nrsk-left-case (Autodesk Fusion 360 design; units mm, degrees)
part number: 2026-11-08-22-34-04-126
part number: 2026-11-09-00-00-46-954
part number: 2026-11-09-00-00-51-869
part number: 2026-11-09-00-01-05-167
part number: 2026-11-09-00-01-07-833
part number: 2026-11-09-00-01-08-673
part number: 2026-11-09-00-01-09-551
part number: 2026-11-09-15-11-48-574
Autodesk Fusion 360 part; units mm, degrees
(part 1 of 3)
sketch "outline" plane through (0, 0, 0) normal (0, 0, 1) x (1, 0, 0) in component "tray"
  line L0 (1, -125.8) -> (154.125, -125.8)
  line L1 (166.625, -113.3) -> (166.625, 5)
  line L2 (154.125, 17.5) -> (1, 17.5)
  line L3 (-11.5, 5) -> (-11.5, -113.3)
  arc A0 (154.125, -125.8) -> (166.625, -113.3) centre (154.125, -113.3) ccw
  arc A1 (166.625, 5) -> (154.125, 17.5) centre (154.125, 5) ccw
  arc A2 (1, 17.5) -> (-11.5, 5) centre (1, 5) ccw
  arc A3 (-11.5, -113.3) -> (1, -125.8) centre (1, -113.3) ccw
extrude "Extrude1" add sketch "outline" along normal blind 14.1 makes body 1 in component "tray"
fillet "Fillet1" radius 2 64 edges at (-7.8388, -122.1388, 0) (77.5625, -125.8, 0) (162.9638, -122.1388, 0) (166.625, -54.15, 0) (162.9638, 13.8388, 0) (77.5625, 17.5, 0) (-7.8388, 13.8388, 0) (-11.5, -54.15, 0) (-11.5, -54.15, 0) (-7.8388, -122.1388, 0) (77.5625, -125.8, 0) (162.9638, -122.1388, 0) (166.625, -54.15, 0) (162.9638, 13.8388, 0) (77.5625, 17.5, 0) (-7.8388, 13.8388, 0) (-7.8388, 13.8388, 0) (-11.5, -54.15, 0) (-7.8388, -122.1388, 0) (77.5625, -125.8, 0) (162.9638, -122.1388, 0) (166.625, -54.15, 0) (162.9638, 13.8388, 0) (77.5625, 17.5, 0) (77.5625, 17.5, 0) (-7.8388, 13.8388, 0) (-11.5, -54.15, 0) (-7.8388, -122.1388, 0) (77.5625, -125.8, 0) (162.9638, -122.1388, 0) (166.625, -54.15, 0) (162.9638, 13.8388, 0) (162.9638, 13.8388, 0) (77.5625, 17.5, 0) (-7.8388, 13.8388, 0) (-11.5, -54.15, 0) (-7.8388, -122.1388, 0) (77.5625, -125.8, 0) (162.9638, -122.1388, 0) (166.625, -54.15, 0) (166.625, -54.15, 0) (162.9638, 13.8388, 0) (77.5625, 17.5, 0) (-7.8388, 13.8388, 0) (-11.5, -54.15, 0) (-7.8388, -122.1388, 0) (77.5625, -125.8, 0) (162.9638, -122.1388, 0) (162.9638, -122.1388, 0) (166.625, -54.15, 0) (162.9638, 13.8388, 0) (77.5625, 17.5, 0) (-7.8388, 13.8388, 0) (-11.5, -54.15, 0) (-7.8388, -122.1388, 0) (77.5625, -125.8, 0) (77.5625, -125.8, 0) (162.9638, -122.1388, 0) (166.625, -54.15, 0) (162.9638, 13.8388, 0) (77.5625, 17.5, 0) (-7.8388, 13.8388, 0) (-11.5, -54.15, 0) (-7.8388, -122.1388, 0) on bodies 1 in component "tray"
fillet "Fillet2" radius 0.6 64 edges at (-7.8388, -122.1388, 14.1) (77.5625, -125.8, 14.1) (162.9638, -122.1388, 14.1) (166.625, -54.15, 14.1) (162.9638, 13.8388, 14.1) (77.5625, 17.5, 14.1) (-7.8388, 13.8388, 14.1) (-11.5, -54.15, 14.1) (77.5625, -125.8, 14.1) (162.9638, -122.1388, 14.1) (166.625, -54.15, 14.1) (162.9638, 13.8388, 14.1) (77.5625, 17.5, 14.1) (-7.8388, 13.8388, 14.1) (-11.5, -54.15, 14.1) (-7.8388, -122.1388, 14.1) (162.9638, -122.1388, 14.1) (166.625, -54.15, 14.1) (162.9638, 13.8388, 14.1) (77.5625, 17.5, 14.1) (-7.8388, 13.8388, 14.1) (-11.5, -54.15, 14.1) (-7.8388, -122.1388, 14.1) (77.5625, -125.8, 14.1) (166.625, -54.15, 14.1) (162.9638, 13.8388, 14.1) (77.5625, 17.5, 14.1) (-7.8388, 13.8388, 14.1) (-11.5, -54.15, 14.1) (-7.8388, -122.1388, 14.1) (77.5625, -125.8, 14.1) (162.9638, -122.1388, 14.1) (162.9638, 13.8388, 14.1) (77.5625, 17.5, 14.1) (-7.8388, 13.8388, 14.1) (-11.5, -54.15, 14.1) (-7.8388, -122.1388, 14.1) (77.5625, -125.8, 14.1) (162.9638, -122.1388, 14.1) (166.625, -54.15, 14.1) (77.5625, 17.5, 14.1) (-7.8388, 13.8388, 14.1) (-11.5, -54.15, 14.1) (-7.8388, -122.1388, 14.1) (77.5625, -125.8, 14.1) (162.9638, -122.1388, 14.1) (166.625, -54.15, 14.1) (162.9638, 13.8388, 14.1) (-7.8388, 13.8388, 14.1) (-11.5, -54.15, 14.1) (-7.8388, -122.1388, 14.1) (77.5625, -125.8, 14.1) (162.9638, -122.1388, 14.1) (166.625, -54.15, 14.1) (162.9638, 13.8388, 14.1) (77.5625, 17.5, 14.1) (-11.5, -54.15, 14.1) (-7.8388, -122.1388, 14.1) (77.5625, -125.8, 14.1) (162.9638, -122.1388, 14.1) (166.625, -54.15, 14.1) (162.9638, 13.8388, 14.1) (77.5625, 17.5, 14.1) (-7.8388, 13.8388, 14.1) on bodies 1 in component "tray"
ref_plane "WorkPlane1" through (0, 0, 2) normal (0, 0, 1) x (1, 0, 0) in component "tray"
sketch "cavity" plane through (0, 0, 2) normal (0, 0, 1) x (1, 0, 0) in component "tray"
  line L0 (1, -117.8) -> (154.125, -117.8)
  line L1 (158.625, -113.3) -> (158.625, 5)
  line L2 (154.125, 9.5) -> (1, 9.5)
  line L3 (-3.5, 5) -> (-3.5, -113.3)
  arc A0 (154.125, -117.8) -> (158.625, -113.3) centre (154.125, -113.3) ccw
  arc A1 (158.625, 5) -> (154.125, 9.5) centre (154.125, 5) ccw
  arc A2 (1, 9.5) -> (-3.5, 5) centre (1, 5) ccw
  arc A3 (-3.5, -113.3) -> (1, -117.8) centre (1, -113.3) ccw
extrude "Extrude2" cut sketch "cavity" along normal blind 14.1 bodies 1 in component "tray"
sketch "bosses" plane through (0, 0, 2) normal (0, 0, 1) x (1, 0, 0) in component "tray"
  circle A0 centre (16, -19.05) radius 2.3
  circle A1 centre (56.5, -19.05) radius 2.3
  circle A2 centre (100.5, -19.05) radius 2.3
  circle A3 centre (132, -19.05) radius 2.3
  circle A4 centre (17, -95.25) radius 2.3
  circle A5 centre (58.5, -95.25) radius 2.3
  circle A6 centre (99.5, -95.25) radius 2.3
  circle A7 centre (142.5, -95.25) radius 2.3
  dimension "d2354" = 4.6
  dimension "d2355" = 4.6
  dimension "d2356" = 4.6
  dimension "d2357" = 4.6
  dimension "d2358" = 4.6
  dimension "d2359" = 4.6
  dimension "d2360" = 4.6
  dimension "d2361" = 4.6
  measures "d2354" diameter of A0
  measures "d2355" diameter of A1
  measures "d2356" diameter of A2
  measures "d2357" diameter of A3
  measures "d2358" diameter of A4
  measures "d2359" diameter of A5
  measures "d2360" diameter of A6
  measures "d2361" diameter of A7
extrude "Extrude3" add sketch "bosses" along normal blind 7 bodies 1 in component "tray"
ref_plane "WorkPlane2" through (0, 0, 0.6) normal (0, 0, 1) x (1, 0, 0) in component "tray"
sketch "pilot holes" plane through (0, 0, 0.6) normal (0, 0, 1) x (1, 0, 0) in component "tray"
  circle A0 centre (16, -19.05) radius 0.8
  circle A1 centre (56.5, -19.05) radius 0.8
  circle A2 centre (100.5, -19.05) radius 0.8
  circle A3 centre (132, -19.05) radius 0.8
  circle A4 centre (17, -95.25) radius 0.8
  circle A5 centre (58.5, -95.25) radius 0.8
  circle A6 centre (99.5, -95.25) radius 0.8
  circle A7 centre (142.5, -95.25) radius 0.8
  dimension "d2366" = 1.6
  dimension "d2367" = 1.6
  dimension "d2368" = 1.6
  dimension "d2369" = 1.6
  dimension "d2370" = 1.6
  dimension "d2371" = 1.6
  dimension "d2372" = 1.6
  dimension "d2373" = 1.6
  measures "d2366" diameter of A0
  measures "d2367" diameter of A1
  measures "d2368" diameter of A2
  measures "d2369" diameter of A3
  measures "d2370" diameter of A4
  measures "d2371" diameter of A5
  measures "d2372" diameter of A6
  measures "d2373" diameter of A7
extrude "Extrude4" cut sketch "pilot holes" along normal blind 8.4 bodies 1 in component "tray"
sketch "screw holes" plane through (0, 0, 0) normal (0, 0, 1) x (1, 0, 0) in component "tray"
  circle A0 centre (-5.0104, -119.3104) radius 1.1
  circle A1 centre (160.1354, -119.3104) radius 1.1
  circle A2 centre (49.2083, 13.5) radius 1.1
  circle A3 centre (49.2083, -121.8) radius 1.1
  circle A4 centre (105.9167, 13.5) radius 1.1
  circle A5 centre (105.9167, -121.8) radius 1.1
  circle A6 centre (-7.5, -54.15) radius 1.1
  circle A7 centre (162.625, -54.15) radius 1.1
  circle A8 centre (19.1438, 13.5) radius 1.1
  circle A9 centre (-7.5, -13.1438) radius 1.1
  dimension "d2376" = 2.2
  dimension "d2377" = 2.2
  dimension "d2378" = 2.2
  dimension "d2379" = 2.2
  dimension "d2380" = 2.2
  dimension "d2381" = 2.2
  dimension "d2382" = 2.2
  dimension "d2383" = 2.2
  dimension "d2384" = 2.2
  dimension "d2385" = 2.2
  measures "d2376" diameter of A0
  measures "d2377" diameter of A1
  measures "d2378" diameter of A2
  measures "d2379" diameter of A3
  measures "d2380" diameter of A4
  measures "d2381" diameter of A5
  measures "d2382" diameter of A6
  measures "d2383" diameter of A7
  measures "d2384" diameter of A8
  measures "d2385" diameter of A9
extrude "Extrude5" cut sketch "screw holes" along normal blind 14.12 bodies 1 in component "tray"
sketch "counterbores" plane through (0, 0, 0) normal (0, 0, 1) x (1, 0, 0) in component "tray"
  circle A0 centre (-5.0104, -119.3104) radius 2.3
  circle A1 centre (160.1354, -119.3104) radius 2.3
  circle A2 centre (49.2083, 13.5) radius 2.3
  circle A3 centre (49.2083, -121.8) radius 2.3
  circle A4 centre (105.9167, 13.5) radius 2.3
  circle A5 centre (105.9167, -121.8) radius 2.3
  circle A6 centre (-7.5, -54.15) radius 2.3
  circle A7 centre (162.625, -54.15) radius 2.3
  circle A8 centre (19.1438, 13.5) radius 2.3
  circle A9 centre (-7.5, -13.1438) radius 2.3
  dimension "d2388" = 4.6
  dimension "d2389" = 4.6
  dimension "d2390" = 4.6
  dimension "d2391" = 4.6
  dimension "d2392" = 4.6
  dimension "d2393" = 4.6
  dimension "d2394" = 4.6
  dimension "d2395" = 4.6
  dimension "d2396" = 4.6
  dimension "d2397" = 4.6
  measures "d2388" diameter of A0
  measures "d2389" diameter of A1
  measures "d2390" diameter of A2
  measures "d2391" diameter of A3
  measures "d2392" diameter of A4
  measures "d2393" diameter of A5
  measures "d2394" diameter of A6
  measures "d2395" diameter of A7
  measures "d2396" diameter of A8
  measures "d2397" diameter of A9
extrude "Extrude6" cut sketch "counterbores" along normal blind 1.6 bodies 1 in component "tray"
ref_plane "WorkPlane3" through (0, 0, 10.9) normal (0, 0, 1) x (1, 0, 0) in component "tray"
sketch "boss pockets" plane through (0, 0, 10.9) normal (0, 0, 1) x (1, 0, 0) in component "tray"
  circle A0 centre (-5.0104, -119.3104) radius 3
  circle A1 centre (160.1354, -119.3104) radius 3
  circle A2 centre (49.2083, 13.5) radius 3
  circle A3 centre (49.2083, -121.8) radius 3
  circle A4 centre (105.9167, 13.5) radius 3
  circle A5 centre (105.9167, -121.8) radius 3
  circle A6 centre (-7.5, -54.15) radius 3
  circle A7 centre (162.625, -54.15) radius 3
  circle A8 centre (19.1438, 13.5) radius 3
  circle A9 centre (-7.5, -13.1438) radius 3
  dimension "d2402" = 6
  dimension "d2403" = 6
  dimension "d2404" = 6
  dimension "d2405" = 6
  dimension "d2406" = 6
  dimension "d2407" = 6
  dimension "d2408" = 6
  dimension "d2409" = 6
  dimension "d2410" = 6
  dimension "d2411" = 6
  measures "d2402" diameter of A0
  measures "d2403" diameter of A1
  measures "d2404" diameter of A2
  measures "d2405" diameter of A3
  measures "d2406" diameter of A4
  measures "d2407" diameter of A5
  measures "d2408" diameter of A6
  measures "d2409" diameter of A7
  measures "d2410" diameter of A8
  measures "d2411" diameter of A9
extrude "Extrude7" cut sketch "boss pockets" along normal blind 3.21 bodies 1 in component "tray"
ref_plane "WorkPlane4" through (0, 0, 9.1) normal (0, 0, 1) x (1, 0, 0) in component "tray"
sketch "nut traps" plane through (0, 0, 9.1) normal (0, 0, 1) x (1, 0, 0) in component "tray"
  line L0 (-2.6144, -119.3104) -> (-3.8124, -117.2354)
  line L1 (-3.8124, -117.2354) -> (-6.2084, -117.2354)
  line L2 (-6.2084, -117.2354) -> (-7.4064, -119.3104)
  line L3 (-7.4064, -119.3104) -> (-6.2084, -121.3854)
  line L4 (-6.2084, -121.3854) -> (-3.8124, -121.3854)
  line L5 (-3.8124, -121.3854) -> (-2.6144, -119.3104)
  line L6 (162.5314, -119.3104) -> (161.3334, -117.2354)
  line L7 (161.3334, -117.2354) -> (158.9374, -117.2354)
  line L8 (158.9374, -117.2354) -> (157.7394, -119.3104)
  line L9 (157.7394, -119.3104) -> (158.9374, -121.3854)
  line L10 (158.9374, -121.3854) -> (161.3334, -121.3854)
  line L11 (161.3334, -121.3854) -> (162.5314, -119.3104)
  line L12 (51.6043, 13.5) -> (50.4063, 15.575)
  line L13 (50.4063, 15.575) -> (48.0103, 15.575)
  line L14 (48.0103, 15.575) -> (46.8123, 13.5)
  line L15 (46.8123, 13.5) -> (48.0103, 11.425)
  line L16 (48.0103, 11.425) -> (50.4063, 11.425)
  line L17 (50.4063, 11.425) -> (51.6043, 13.5)
  line L18 (51.6043, -121.8) -> (50.4063, -119.725)
  line L19 (50.4063, -119.725) -> (48.0103, -119.725)
  line L20 (48.0103, -119.725) -> (46.8123, -121.8)
  line L21 (46.8123, -121.8) -> (48.0103, -123.875)
  line L22 (48.0103, -123.875) -> (50.4063, -123.875)
  line L23 (50.4063, -123.875) -> (51.6043, -121.8)
  line L24 (108.3127, 13.5) -> (107.1147, 15.575)
  line L25 (107.1147, 15.575) -> (104.7187, 15.575)
  line L26 (104.7187, 15.575) -> (103.5207, 13.5)
  line L27 (103.5207, 13.5) -> (104.7187, 11.425)
  line L28 (104.7187, 11.425) -> (107.1147, 11.425)
  line L29 (107.1147, 11.425) -> (108.3127, 13.5)
  line L30 (108.3127, -121.8) -> (107.1147, -119.725)
  line L31 (107.1147, -119.725) -> (104.7187, -119.725)
  line L32 (104.7187, -119.725) -> (103.5207, -121.8)
  line L33 (103.5207, -121.8) -> (104.7187, -123.875)
  line L34 (104.7187, -123.875) -> (107.1147, -123.875)
  line L35 (107.1147, -123.875) -> (108.3127, -121.8)
  line L36 (-5.104, -54.15) -> (-6.302, -52.075)
  line L37 (-6.302, -52.075) -> (-8.698, -52.075)
  line L38 (-8.698, -52.075) -> (-9.896, -54.15)
  line L39 (-9.896, -54.15) -> (-8.698, -56.225)
  line L40 (-8.698, -56.225) -> (-6.302, -56.225)
  line L41 (-6.302, -56.225) -> (-5.104, -54.15)
  line L42 (165.021, -54.15) -> (163.823, -52.075)
  line L43 (163.823, -52.075) -> (161.427, -52.075)
  line L44 (161.427, -52.075) -> (160.229, -54.15)
  line L45 (160.229, -54.15) -> (161.427, -56.225)
  line L46 (161.427, -56.225) -> (163.823, -56.225)
  line L47 (163.823, -56.225) -> (165.021, -54.15)
  line L48 (21.5398, 13.5) -> (20.3418, 15.575)
  line L49 (20.3418, 15.575) -> (17.9458, 15.575)
  line L50 (17.9458, 15.575) -> (16.7478, 13.5)
  line L51 (16.7478, 13.5) -> (17.9458, 11.425)
  line L52 (17.9458, 11.425) -> (20.3418, 11.425)
  line L53 (20.3418, 11.425) -> (21.5398, 13.5)
  line L54 (-5.104, -13.1438) -> (-6.302, -11.0688)
  line L55 (-6.302, -11.0688) -> (-8.698, -11.0688)
  line L56 (-8.698, -11.0688) -> (-9.896, -13.1438)
  line L57 (-9.896, -13.1438) -> (-8.698, -15.2188)
  line L58 (-8.698, -15.2188) -> (-6.302, -15.2188)
  line L59 (-6.302, -15.2188) -> (-5.104, -13.1438)
  constraint coincident L0.end L1.start
  constraint coincident L1.end L2.start
  constraint coincident L2.end L3.start
  constraint coincident L3.end L4.start
  constraint coincident L4.end L5.start
  constraint coincident L0.start L5.end
  constraint coincident L6.end L7.start
  constraint coincident L7.end L8.start
  constraint coincident L8.end L9.start
  constraint coincident L9.end L10.start
  constraint coincident L10.end L11.start
  constraint coincident L6.start L11.end
  constraint coincident L12.end L13.start
  constraint coincident L13.end L14.start
  constraint coincident L14.end L15.start
  constraint coincident L15.end L16.start
  constraint coincident L16.end L17.start
  constraint coincident L12.start L17.end
  constraint coincident L18.end L19.start
  constraint coincident L19.end L20.start
  constraint coincident L20.end L21.start
  constraint coincident L21.end L22.start
  constraint coincident L22.end L23.start
  constraint coincident L18.start L23.end
  constraint coincident L24.end L25.start
  constraint coincident L25.end L26.start
  constraint coincident L26.end L27.start
  constraint coincident L27.end L28.start
  constraint coincident L28.end L29.start
  constraint coincident L24.start L29.end
  constraint coincident L30.end L31.start
  constraint coincident L31.end L32.start
  constraint coincident L32.end L33.start
  constraint coincident L33.end L34.start
  constraint coincident L34.end L35.start
  constraint coincident L30.start L35.end
  constraint coincident L36.end L37.start
  constraint coincident L37.end L38.start
  constraint coincident L38.end L39.start
  constraint coincident L39.end L40.start
  constraint coincident L40.end L41.start
  constraint coincident L36.start L41.end
  constraint coincident L42.end L43.start
  constraint coincident L43.end L44.start
  constraint coincident L44.end L45.start
  constraint coincident L45.end L46.start
  constraint coincident L46.end L47.start
  constraint coincident L42.start L47.end
  constraint coincident L48.end L49.start
  constraint coincident L49.end L50.start
  constraint coincident L50.end L51.start
  constraint coincident L51.end L52.start
  constraint coincident L52.end L53.start
  constraint coincident L48.start L53.end
  constraint coincident L54.end L55.start
  constraint coincident L55.end L56.start
  constraint coincident L56.end L57.start
  constraint coincident L57.end L58.start
  constraint coincident L58.end L59.start
  constraint coincident L54.start L59.end
extrude "Extrude8" cut sketch "nut traps" along normal blind 1.81 bodies 1 in component "tray"
ref_plane "WorkPlane5" through (0, 0, 2) normal (0, 0, 1) x (1, 0, 0) in component "tray"
sketch "wheel opening" plane through (0, 0, 2) normal (0, 0, 1) x (1, 0, 0) in component "tray"
  circle A0 centre (2, 4) radius 15.2
extrude "Extrude9" cut sketch "wheel opening" along normal blind 4.8 bodies 1 in component "tray"
ref_plane "WorkPlane6" through (0, 0, 6.8) normal (0, 0, 1) x (1, 0, 0) in component "tray"
sketch "cap lower tier" plane through (0, 0, 6.8) normal (0, 0, 1) x (1, 0, 0) in component "tray"
  circle A0 centre (2, 4) radius 15.2
extrude "Extrude10" cut sketch "cap lower tier" along normal blind 4.3 bodies 1 in component "tray"
ref_plane "WorkPlane7" through (0, 0, 11.1) normal (0, 0, 1) x (1, 0, 0) in component "tray"
sketch "cap shoulder" plane through (0, 0, 11.1) normal (0, 0, 1) x (1, 0, 0) in component "tray"
  circle A0 centre (2, 4) radius 17.2
extrude "Extrude11" cut sketch "cap shoulder" along normal blind 3.1 bodies 1 in component "tray"
ref_plane "WorkPlane8" through (0, 0, 13.6) normal (0, 0, 1) x (1, 0, 0) in component "tray"
sketch "cover step" plane through (0, 0, 13.6) normal (0, 0, 1) x (1, 0, 0) in component "tray"
  line L0 (145.325, -35.995) -> (154.125, -35.995)
  line L1 (161.225, -28.895) -> (161.225, 5)
  line L2 (154.125, 12.1) -> (145.325, 12.1)
  line L3 (138.225, 5) -> (138.225, -28.895)
  arc A0 (154.125, -35.995) -> (161.225, -28.895) centre (154.125, -28.895) ccw
  arc A1 (161.225, 5) -> (154.125, 12.1) centre (154.125, 5) ccw
  arc A2 (145.325, 12.1) -> (138.225, 5) centre (145.325, 5) ccw
  arc A3 (138.225, -28.895) -> (145.325, -35.995) centre (145.325, -28.895) ccw
extrude "Extrude12" cut sketch "cover step" along normal blind 0.51 bodies 1 in component "tray"
ref_plane "WorkPlane9" through (0, 0, 5.54) normal (0, 0, 1) x (1, 0, 0) in component "tray"
sketch "usb tunnel" plane through (0, 0, 5.54) normal (0, 0, 1) x (1, 0, 0) in component "tray"
  line L0 (128.79, 8.7) -> (129.425, 8.7)
  line L1 (129.425, 8.7) -> (129.425, 16.5)
  line L2 (129.425, 16.5) -> (128.79, 16.5)
  line L3 (128.79, 16.5) -> (128.79, 16.7)
  line L4 (128.79, 16.7) -> (117.46, 16.7)
  line L5 (117.46, 16.7) -> (117.46, 16.5)
  line L6 (117.46, 16.5) -> (116.825, 16.5)
  line L7 (116.825, 16.5) -> (116.825, 8.7)
  line L8 (116.825, 8.7) -> (117.46, 8.7)
  line L9 (117.46, 8.7) -> (117.46, 6.89)
  line L10 (117.46, 6.89) -> (128.79, 6.89)
  line L11 (128.79, 6.89) -> (128.79, 8.7)
  constraint coincident L0.end L1.start
  constraint coincident L1.end L2.start
  constraint coincident L2.end L3.start
  constraint coincident L3.end L4.start
  constraint coincident L4.end L5.start
  constraint coincident L5.end L6.start
  constraint coincident L6.end L7.start
  constraint coincident L7.end L8.start
  constraint coincident L8.end L9.start
  constraint coincident L9.end L10.start
  constraint coincident L10.end L11.start
  constraint coincident L0.start L11.end
extrude "Extrude13" cut sketch "usb tunnel" along normal blind 7.36 bodies 1 in component "tray"
ref_plane "WorkPlane10" through (0, 15.7, 0) normal (0, 1, 0) x (0, 0, 1) in component "tray"
sketch "usb opening" plane through (0, 15.7, 0) normal (0, 1, 0) x (1, 0, 0) in component "tray"
  line L0 (120.285, -5.54) -> (125.965, -5.54)
  line L1 (125.965, -9.2) -> (120.285, -9.2)
  arc A0 (125.965, -9.2) -> (125.965, -5.54) centre (125.965, -7.37) ccw
  arc A1 (120.285, -5.54) -> (120.285, -9.2) centre (120.285, -7.37) ccw
extrude "Extrude14" cut sketch "usb opening" along normal blind 2.8 bodies 1 in component "tray"
ref_plane "WorkPlane11" through (0, 0, 5.54) normal (0, 0, 1) x (1, 0, 0) in component "tray"
sketch "link tunnel" plane through (0, 0, 5.54) normal (0, 0, 1) x (1, 0, 0) in component "tray"
  line L0 (146.79, 8.7) -> (147.425, 8.7)
  line L1 (147.425, 8.7) -> (147.425, 16.5)
  line L2 (147.425, 16.5) -> (146.79, 16.5)
  line L3 (146.79, 16.5) -> (146.79, 16.7)
  line L4 (146.79, 16.7) -> (135.46, 16.7)
  line L5 (135.46, 16.7) -> (135.46, 16.5)
  line L6 (135.46, 16.5) -> (134.825, 16.5)
  line L7 (134.825, 16.5) -> (134.825, 8.7)
  line L8 (134.825, 8.7) -> (135.46, 8.7)
  line L9 (135.46, 8.7) -> (135.46, 6.89)
  line L10 (135.46, 6.89) -> (146.79, 6.89)
  line L11 (146.79, 6.89) -> (146.79, 8.7)
  constraint coincident L0.end L1.start
  constraint coincident L1.end L2.start
  constraint coincident L2.end L3.start
  constraint coincident L3.end L4.start
  constraint coincident L4.end L5.start
  constraint coincident L5.end L6.start
  constraint coincident L6.end L7.start
  constraint coincident L7.end L8.start
  constraint coincident L8.end L9.start
  constraint coincident L9.end L10.start
  constraint coincident L10.end L11.start
  constraint coincident L0.start L11.end
extrude "Extrude15" cut sketch "link tunnel" along normal blind 7.36 bodies 1 in component "tray"
ref_plane "WorkPlane12" through (0, 15.7, 0) normal (0, 1, 0) x (0, 0, 1) in component "tray"
sketch "link opening" plane through (0, 15.7, 0) normal (0, 1, 0) x (1, 0, 0) in component "tray"
  line L0 (138.285, -5.54) -> (143.965, -5.54)
  line L1 (143.965, -9.2) -> (138.285, -9.2)
  arc A0 (143.965, -9.2) -> (143.965, -5.54) centre (143.965, -7.37) ccw
  arc A1 (138.285, -5.54) -> (138.285, -9.2) centre (138.285, -7.37) ccw
extrude "Extrude16" cut sketch "link opening" along normal blind 2.8 bodies 1 in component "tray"
sketch "wheel post" plane through (0, 0, 2) normal (0, 0, 1) x (1, 0, 0) in component "tray"
  circle A0 centre (2, 4) radius 1.8
  dimension "d2450" = 3.6
  measures "d2450" diameter of A0
extrude "Extrude17" add sketch "wheel post" along normal blind 2 bodies 1 in component "tray"
sketch "reset" plane through (0, 0, 0) normal (0, 0, 1) x (1, 0, 0) in component "tray"
  circle A0 centre (136.125, -35.95) radius 1.5
  dimension "d2453" = 3
  measures "d2453" diameter of A0
extrude "Extrude18" cut sketch "reset" along normal blind 2.02 bodies 1 in component "tray"
sketch "foot recesses" plane through (0, 0, 0) normal (0, 0, 1) x (1, 0, 0) in component "tray"
  circle A0 centre (26.5, 9.5) radius 5
  circle A1 centre (156.125, 9.5) radius 5
  circle A2 centre (3.5, -117.8) radius 5
  circle A3 centre (151.625, -117.8) radius 5
  circle A4 centre (-3.5, -20.5) radius 5
  dimension "d2456" = 10
  dimension "d2457" = 10
  dimension "d2458" = 10
  dimension "d2459" = 10
  dimension "d2460" = 10
  measures "d2456" diameter of A0
  measures "d2457" diameter of A1
  measures "d2458" diameter of A2
  measures "d2459" diameter of A3
  measures "d2460" diameter of A4
extrude "Extrude19" cut sketch "foot recesses" along normal blind 1 bodies 1 in component "tray"
sketch "outline (2)" plane through (0, 0, 0) normal (0, 0, 1) x (1, 0, 0) in component "plate"
  line L0 (1, -125.8) -> (154.125, -125.8)
  line L1 (166.625, -113.3) -> (166.625, 5)
  line L2 (154.125, 17.5) -> (1, 17.5)
  line L3 (-11.5, 5) -> (-11.5, -113.3)
  arc A0 (154.125, -125.8) -> (166.625, -113.3) centre (154.125, -113.3) ccw
  arc A1 (166.625, 5) -> (154.125, 17.5) centre (154.125, 5) ccw
  arc A2 (1, 17.5) -> (-11.5, 5) centre (1, 5) ccw
  arc A3 (-11.5, -113.3) -> (1, -125.8) centre (1, -113.3) ccw
extrude "Extrude1'" add sketch "outline (2)" along normal blind 1.5 separate body makes body 2 in component "plate"
fillet "Fillet1'" radius 1 64 edges at (-7.8388, -122.1388, 1.5) (77.5625, -125.8, 1.5) (162.9638, -122.1388, 1.5) (166.625, -54.15, 1.5) (162.9638, 13.8388, 1.5) (77.5625, 17.5, 1.5) (-7.8388, 13.8388, 1.5) (-11.5, -54.15, 1.5) (77.5625, -125.8, 1.5) (162.9638, -122.1388, 1.5) (166.625, -54.15, 1.5) (162.9638, 13.8388, 1.5) (77.5625, 17.5, 1.5) (-7.8388, 13.8388, 1.5) (-11.5, -54.15, 1.5) (-7.8388, -122.1388, 1.5) (162.9638, -122.1388, 1.5) (166.625, -54.15, 1.5) (162.9638, 13.8388, 1.5) (77.5625, 17.5, 1.5) (-7.8388, 13.8388, 1.5) (-11.5, -54.15, 1.5) (-7.8388, -122.1388, 1.5) (77.5625, -125.8, 1.5) (166.625, -54.15, 1.5) (162.9638, 13.8388, 1.5) (77.5625, 17.5, 1.5) (-7.8388, 13.8388, 1.5) (-11.5, -54.15, 1.5) (-7.8388, -122.1388, 1.5) (77.5625, -125.8, 1.5) (162.9638, -122.1388, 1.5) (162.9638, 13.8388, 1.5) (77.5625, 17.5, 1.5) (-7.8388, 13.8388, 1.5) (-11.5, -54.15, 1.5) (-7.8388, -122.1388, 1.5) (77.5625, -125.8, 1.5) (162.9638, -122.1388, 1.5) (166.625, -54.15, 1.5) (77.5625, 17.5, 1.5) (-7.8388, 13.8388, 1.5) (-11.5, -54.15, 1.5) (-7.8388, -122.1388, 1.5) (77.5625, -125.8, 1.5) (162.9638, -122.1388, 1.5) (166.625, -54.15, 1.5) (162.9638, 13.8388, 1.5) (-7.8388, 13.8388, 1.5) (-11.5, -54.15, 1.5) (-7.8388, -122.1388, 1.5) (77.5625, -125.8, 1.5) (162.9638, -122.1388, 1.5) (166.625, -54.15, 1.5) (162.9638, 13.8388, 1.5) (77.5625, 17.5, 1.5) (-11.5, -54.15, 1.5) (-7.8388, -122.1388, 1.5) (77.5625, -125.8, 1.5) (162.9638, -122.1388, 1.5) (166.625, -54.15, 1.5) (162.9638, 13.8388, 1.5) (77.5625, 17.5, 1.5) (-7.8388, 13.8388, 1.5) on bodies 2 in component "plate"
sketch "switch cut-outs" plane through (0, 0, 0) normal (0, 0, 1) x (1, 0, 0) in component "plate"
  line L0 (2.525, -16.525) -> (16.525, -16.525)
  line L1 (16.525, -16.525) -> (16.525, -2.525)
  line L2 (16.525, -2.525) -> (2.525, -2.525)
  line L3 (2.525, -2.525) -> (2.525, -16.525)
  line L4 (21.575, -16.525) -> (35.575, -16.525)
  line L5 (35.575, -16.525) -> (35.575, -2.525)
  line L6 (35.575, -2.525) -> (21.575, -2.525)
  line L7 (21.575, -2.525) -> (21.575, -16.525)
  line L8 (40.625, -16.525) -> (54.625, -16.525)
  line L9 (54.625, -16.525) -> (54.625, -2.525)
  line L10 (54.625, -2.525) -> (40.625, -2.525)
  line L11 (40.625, -2.525) -> (40.625, -16.525)
  line L12 (59.675, -16.525) -> (73.675, -16.525)
  line L13 (73.675, -16.525) -> (73.675, -2.525)
  line L14 (73.675, -2.525) -> (59.675, -2.525)
  line L15 (59.675, -2.525) -> (59.675, -16.525)
  line L16 (78.725, -16.525) -> (92.725, -16.525)
  line L17 (92.725, -16.525) -> (92.725, -2.525)
  line L18 (92.725, -2.525) -> (78.725, -2.525)
  line L19 (78.725, -2.525) -> (78.725, -16.525)
  line L20 (97.775, -16.525) -> (111.775, -16.525)
  line L21 (111.775, -16.525) -> (111.775, -2.525)
  line L22 (111.775, -2.525) -> (97.775, -2.525)
  line L23 (97.775, -2.525) -> (97.775, -16.525)
  line L24 (116.825, -16.525) -> (130.825, -16.525)
  line L25 (130.825, -16.525) -> (130.825, -2.525)
  line L26 (130.825, -2.525) -> (116.825, -2.525)
  line L27 (116.825, -2.525) -> (116.825, -16.525)
  line L28 (2.525, -35.575) -> (16.525, -35.575)
  line L29 (16.525, -35.575) -> (16.525, -21.575)
  line L30 (16.525, -21.575) -> (2.525, -21.575)
  line L31 (2.525, -21.575) -> (2.525, -35.575)
  line L32 (21.575, -35.575) -> (35.575, -35.575)
  line L33 (35.575, -35.575) -> (35.575, -21.575)
  line L34 (35.575, -21.575) -> (21.575, -21.575)
  line L35 (21.575, -21.575) -> (21.575, -35.575)
  line L36 (40.625, -35.575) -> (54.625, -35.575)
  line L37 (54.625, -35.575) -> (54.625, -21.575)
  line L38 (54.625, -21.575) -> (40.625, -21.575)
  line L39 (40.625, -21.575) -> (40.625, -35.575)
  line L40 (59.675, -35.575) -> (73.675, -35.575)
  line L41 (73.675, -35.575) -> (73.675, -21.575)
  line L42 (73.675, -21.575) -> (59.675, -21.575)
  line L43 (59.675, -21.575) -> (59.675, -35.575)
  line L44 (78.725, -35.575) -> (92.725, -35.575)
  line L45 (92.725, -35.575) -> (92.725, -21.575)
  line L46 (92.725, -21.575) -> (78.725, -21.575)
  line L47 (78.725, -21.575) -> (78.725, -35.575)
  line L48 (97.775, -35.575) -> (111.775, -35.575)
  line L49 (111.775, -35.575) -> (111.775, -21.575)
  line L50 (111.775, -21.575) -> (97.775, -21.575)
  line L51 (97.775, -21.575) -> (97.775, -35.575)
  line L52 (116.825, -35.575) -> (130.825, -35.575)
  line L53 (130.825, -35.575) -> (130.825, -21.575)
  line L54 (130.825, -21.575) -> (116.825, -21.575)
  line L55 (116.825, -21.575) -> (116.825, -35.575)
  line L56 (7.288, -54.625) -> (21.288, -54.625)
  line L57 (21.288, -54.625) -> (21.288, -40.625)
  line L58 (21.288, -40.625) -> (7.288, -40.625)
  line L59 (7.288, -40.625) -> (7.288, -54.625)
  line L60 (31.1, -54.625) -> (45.1, -54.625)
  line L61 (45.1, -54.625) -> (45.1, -40.625)
  line L62 (45.1, -40.625) -> (31.1, -40.625)
  line L63 (31.1, -40.625) -> (31.1, -54.625)
  line L64 (50.15, -54.625) -> (64.15, -54.625)
  line L65 (64.15, -54.625) -> (64.15, -40.625)
  line L66 (64.15, -40.625) -> (50.15, -40.625)
  line L67 (50.15, -40.625) -> (50.15, -54.625)
  line L68 (69.2, -54.625) -> (83.2, -54.625)
  line L69 (83.2, -54.625) -> (83.2, -40.625)
  line L70 (83.2, -40.625) -> (69.2, -40.625)
  line L71 (69.2, -40.625) -> (69.2, -54.625)
  line L72 (88.25, -54.625) -> (102.25, -54.625)
  line L73 (102.25, -54.625) -> (102.25, -40.625)
  line L74 (102.25, -40.625) -> (88.25, -40.625)
  line L75 (88.25, -40.625) -> (88.25, -54.625)
  line L76 (107.3, -54.625) -> (121.3, -54.625)
  line L77 (121.3, -54.625) -> (121.3, -40.625)
  line L78 (121.3, -40.625) -> (107.3, -40.625)
  line L79 (107.3, -40.625) -> (107.3, -54.625)
  line L80 (9.669, -73.675) -> (23.669, -73.675)
  line L81 (23.669, -73.675) -> (23.669, -59.675)
  line L82 (23.669, -59.675) -> (9.669, -59.675)
  line L83 (9.669, -59.675) -> (9.669, -73.675)
  line L84 (35.863, -73.675) -> (49.863, -73.675)
  line L85 (49.863, -73.675) -> (49.863, -59.675)
  line L86 (49.863, -59.675) -> (35.863, -59.675)
  line L87 (35.863, -59.675) -> (35.863, -73.675)
  line L88 (54.913, -73.675) -> (68.913, -73.675)
  line L89 (68.913, -73.675) -> (68.913, -59.675)
  line L90 (68.913, -59.675) -> (54.913, -59.675)
  line L91 (54.913, -59.675) -> (54.913, -73.675)
  line L92 (73.963, -73.675) -> (87.963, -73.675)
  line L93 (87.963, -73.675) -> (87.963, -59.675)
  line L94 (87.963, -59.675) -> (73.963, -59.675)
  line L95 (73.963, -59.675) -> (73.963, -73.675)
  line L96 (93.013, -73.675) -> (107.013, -73.675)
  line L97 (107.013, -73.675) -> (107.013, -59.675)
  line L98 (107.013, -59.675) -> (93.013, -59.675)
  line L99 (93.013, -59.675) -> (93.013, -73.675)
  line L100 (112.062, -73.675) -> (126.062, -73.675)
  line L101 (126.062, -73.675) -> (126.062, -59.675)
  line L102 (126.062, -59.675) -> (112.062, -59.675)
  line L103 (112.062, -59.675) -> (112.062, -73.675)
  line L104 (14.431, -92.725) -> (28.431, -92.725)
  line L105 (28.431, -92.725) -> (28.431, -78.725)
  line L106 (28.431, -78.725) -> (14.431, -78.725)
  line L107 (14.431, -78.725) -> (14.431, -92.725)
  line L108 (5.993, -93.925) -> (12.993, -93.925)
  line L109 (12.993, -93.925) -> (12.993, -78.525)
  line L110 (12.993, -78.525) -> (5.993, -78.525)
  line L111 (5.993, -78.525) -> (5.993, -93.925)
  line L112 (29.869, -93.925) -> (36.869, -93.925)
  line L113 (36.869, -93.925) -> (36.869, -78.525)
  line L114 (36.869, -78.525) -> (29.869, -78.525)
  line L115 (29.869, -78.525) -> (29.869, -93.925)
  line L116 (45.388, -92.725) -> (59.388, -92.725)
  line L117 (59.388, -92.725) -> (59.388, -78.725)
  line L118 (59.388, -78.725) -> (45.388, -78.725)
  line L119 (45.388, -78.725) -> (45.388, -92.725)
  line L120 (64.438, -92.725) -> (78.438, -92.725)
  line L121 (78.438, -92.725) -> (78.438, -78.725)
  line L122 (78.438, -78.725) -> (64.438, -78.725)
  line L123 (64.438, -78.725) -> (64.438, -92.725)
  line L124 (83.487, -92.725) -> (97.487, -92.725)
  line L125 (97.487, -92.725) -> (97.487, -78.725)
  line L126 (97.487, -78.725) -> (83.487, -78.725)
  line L127 (83.487, -78.725) -> (83.487, -92.725)
  line L128 (102.538, -92.725) -> (116.538, -92.725)
  line L129 (116.538, -92.725) -> (116.538, -78.725)
  line L130 (116.538, -78.725) -> (102.538, -78.725)
  line L131 (102.538, -78.725) -> (102.538, -92.725)
  line L132 (121.588, -92.725) -> (135.588, -92.725)
  line L133 (135.588, -92.725) -> (135.588, -78.725)
  line L134 (135.588, -78.725) -> (121.588, -78.725)
  line L135 (121.588, -78.725) -> (121.588, -92.725)
  line L136 (14.431, -111.775) -> (28.431, -111.775)
  line L137 (28.431, -111.775) -> (28.431, -97.775)
  line L138 (28.431, -97.775) -> (14.431, -97.775)
  line L139 (14.431, -97.775) -> (14.431, -111.775)
  line L140 (38.244, -111.775) -> (52.244, -111.775)
  line L141 (52.244, -111.775) -> (52.244, -97.775)
  line L142 (52.244, -97.775) -> (38.244, -97.775)
  line L143 (38.244, -97.775) -> (38.244, -111.775)
  line L144 (62.056, -111.775) -> (76.056, -111.775)
  line L145 (76.056, -111.775) -> (76.056, -97.775)
  line L146 (76.056, -97.775) -> (62.056, -97.775)
  line L147 (62.056, -97.775) -> (62.056, -111.775)
  line L148 (83.487, -111.775) -> (97.487, -111.775)
  line L149 (97.487, -111.775) -> (97.487, -97.775)
  line L150 (97.487, -97.775) -> (83.487, -97.775)
  line L151 (83.487, -97.775) -> (83.487, -111.775)
  line L152 (102.538, -111.775) -> (116.538, -111.775)
  line L153 (116.538, -111.775) -> (116.538, -97.775)
  line L154 (116.538, -97.775) -> (102.538, -97.775)
  line L155 (102.538, -97.775) -> (102.538, -111.775)
  line L156 (121.588, -111.775) -> (135.588, -111.775)
  line L157 (135.588, -111.775) -> (135.588, -97.775)
  line L158 (135.588, -97.775) -> (121.588, -97.775)
  line L159 (121.588, -97.775) -> (121.588, -111.775)
  line L160 (145.325, -35.995) -> (154.125, -35.995)
  line L161 (161.225, -28.895) -> (161.225, 5)
  line L162 (154.125, 12.1) -> (145.325, 12.1)
  line L163 (138.225, 5) -> (138.225, -28.895)
  arc A0 (154.125, -35.995) -> (161.225, -28.895) centre (154.125, -28.895) ccw
  arc A1 (161.225, 5) -> (154.125, 12.1) centre (154.125, 5) ccw
  arc A2 (145.325, 12.1) -> (138.225, 5) centre (145.325, 5) ccw
  arc A3 (138.225, -28.895) -> (145.325, -35.995) centre (145.325, -28.895) ccw
  constraint coincident L0.end L1.start
  constraint coincident L1.end L2.start
  constraint coincident L2.end L3.start
  constraint coincident L0.start L3.end
  constraint coincident L4.end L5.start
  constraint coincident L5.end L6.start
  constraint coincident L6.end L7.start
  constraint coincident L4.start L7.end
  constraint coincident L8.end L9.start
  constraint coincident L9.end L10.start
  constraint coincident L10.end L11.start
  constraint coincident L8.start L11.end
  constraint coincident L12.end L13.start
  constraint coincident L13.end L14.start
  constraint coincident L14.end L15.start
  constraint coincident L12.start L15.end
  constraint coincident L16.end L17.start
  constraint coincident L17.end L18.start
  constraint coincident L18.end L19.start
  constraint coincident L16.start L19.end
  constraint coincident L20.end L21.start
  constraint coincident L21.end L22.start
  constraint coincident L22.end L23.start
  constraint coincident L20.start L23.end
  constraint coincident L24.end L25.start
  constraint coincident L25.end L26.start
  constraint coincident L26.end L27.start
  constraint coincident L24.start L27.end
  constraint coincident L28.end L29.start
  constraint coincident L29.end L30.start
  constraint coincident L30.end L31.start
  constraint coincident L28.start L31.end
  constraint coincident L32.end L33.start
  constraint coincident L33.end L34.start
  constraint coincident L34.end L35.start
  constraint coincident L32.start L35.end
  constraint coincident L36.end L37.start
  constraint coincident L37.end L38.start
  constraint coincident L38.end L39.start
  constraint coincident L36.start L39.end
  constraint coincident L40.end L41.start
  constraint coincident L41.end L42.start
  constraint coincident L42.end L43.start
  constraint coincident L40.start L43.end
  constraint coincident L44.end L45.start
  constraint coincident L45.end L46.start
  constraint coincident L46.end L47.start
  constraint coincident L44.start L47.end
  constraint coincident L48.end L49.start
  constraint coincident L49.end L50.start
  constraint coincident L50.end L51.start
  constraint coincident L48.start L51.end
  constraint coincident L52.end L53.start
  constraint coincident L53.end L54.start
  constraint coincident L54.end L55.start
  constraint coincident L52.start L55.end
  constraint coincident L56.end L57.start
  constraint coincident L57.end L58.start
  constraint coincident L58.end L59.start
  constraint coincident L56.start L59.end
  constraint coincident L60.end L61.start
  constraint coincident L61.end L62.start
  constraint coincident L62.end L63.start
  constraint coincident L60.start L63.end
  constraint coincident L64.end L65.start
  constraint coincident L65.end L66.start
  constraint coincident L66.end L67.start
  constraint coincident L64.start L67.end
  constraint coincident L68.end L69.start
  constraint coincident L69.end L70.start
  constraint coincident L70.end L71.start
  constraint coincident L68.start L71.end
  constraint coincident L72.end L73.start
  constraint coincident L73.end L74.start
  constraint coincident L74.end L75.start
  constraint coincident L72.start L75.end
  constraint coincident L76.end L77.start
  constraint coincident L77.end L78.start
  constraint coincident L78.end L79.start
  constraint coincident L76.start L79.end
  constraint coincident L80.end L81.start
  constraint coincident L81.end L82.start
  constraint coincident L82.end L83.start
  constraint coincident L80.start L83.end
  constraint coincident L84.end L85.start
  constraint coincident L85.end L86.start
  constraint coincident L86.end L87.start
  constraint coincident L84.start L87.end
  constraint coincident L88.end L89.start
  constraint coincident L89.end L90.start
  constraint coincident L90.end L91.start
  constraint coincident L88.start L91.end
  constraint coincident L92.end L93.start
  constraint coincident L93.end L94.start
  constraint coincident L94.end L95.start
  constraint coincident L92.start L95.end
  constraint coincident L96.end L97.start
  constraint coincident L97.end L98.start
  constraint coincident L98.end L99.start
  constraint coincident L96.start L99.end
  constraint coincident L100.end L101.start
  constraint coincident L101.end L102.start
  constraint coincident L102.end L103.start
  constraint coincident L100.start L103.end
  constraint coincident L104.end L105.start
  constraint coincident L105.end L106.start
  constraint coincident L106.end L107.start
  constraint coincident L104.start L107.end
  constraint coincident L108.end L109.start
  constraint coincident L109.end L110.start
  constraint coincident L110.end L111.start
  constraint coincident L108.start L111.end
  constraint coincident L112.end L113.start
  constraint coincident L113.end L114.start
  constraint coincident L114.end L115.start
  constraint coincident L112.start L115.end
  constraint coincident L116.end L117.start
  constraint coincident L117.end L118.start
  constraint coincident L118.end L119.start
  constraint coincident L116.start L119.end
  constraint coincident L120.end L121.start
  constraint coincident L121.end L122.start
  constraint coincident L122.end L123.start
  constraint coincident L120.start L123.end
  constraint coincident L124.end L125.start
  constraint coincident L125.end L126.start
  constraint coincident L126.end L127.start
  constraint coincident L124.start L127.end
  constraint coincident L128.end L129.start
  constraint coincident L129.end L130.start
  constraint coincident L130.end L131.start
  constraint coincident L128.start L131.end
  constraint coincident L132.end L133.start
  constraint coincident L133.end L134.start
  constraint coincident L134.end L135.start
  constraint coincident L132.start L135.end
  constraint coincident L136.end L137.start
  constraint coincident L137.end L138.start
  constraint coincident L138.end L139.start
  constraint coincident L136.start L139.end
  constraint coincident L140.end L141.start
  constraint coincident L141.end L142.start
  constraint coincident L142.end L143.start
  constraint coincident L140.start L143.end
  constraint coincident L144.end L145.start
  constraint coincident L145.end L146.start
  constraint coincident L146.end L147.start
  constraint coincident L144.start L147.end
  constraint coincident L148.end L149.start
  constraint coincident L149.end L150.start
  constraint coincident L150.end L151.start
  constraint coincident L148.start L151.end
  constraint coincident L152.end L153.start
  constraint coincident L153.end L154.start
  constraint coincident L154.end L155.start
  constraint coincident L152.start L155.end
  constraint coincident L156.end L157.start
  constraint coincident L157.end L158.start
  constraint coincident L158.end L159.start
  constraint coincident L156.start L159.end
extrude "Extrude2'" cut sketch "switch cut-outs" along normal blind 1.6 bodies 2 in component "plate"
ref_plane "WorkPlane1" through (0, 0, -2.1) normal (0, 0, 1) x (1, 0, 0) in component "plate"
sketch "web" plane through (0, 0, 0) normal (0, 0, 1) x (1, 0, 0) in component "plate"
  line L0 (1, -117.5) -> (154.125, -117.5)
  line L1 (158.325, -113.3) -> (158.325, 5)
  line L2 (154.125, 9.2) -> (1, 9.2)
  line L3 (-3.2, 5) -> (-3.2, -113.3)
  arc A0 (154.125, -117.5) -> (158.325, -113.3) centre (154.125, -113.3) ccw
  arc A1 (158.325, 5) -> (154.125, 9.2) centre (154.125, 5) ccw
  arc A2 (1, 9.2) -> (-3.2, 5) centre (1, 5) ccw
  arc A3 (-3.2, -113.3) -> (1, -117.5) centre (1, -113.3) ccw
extrude "Extrude3'" add sketch "web" against normal blind 2 separate body makes body 3 in component "plate"